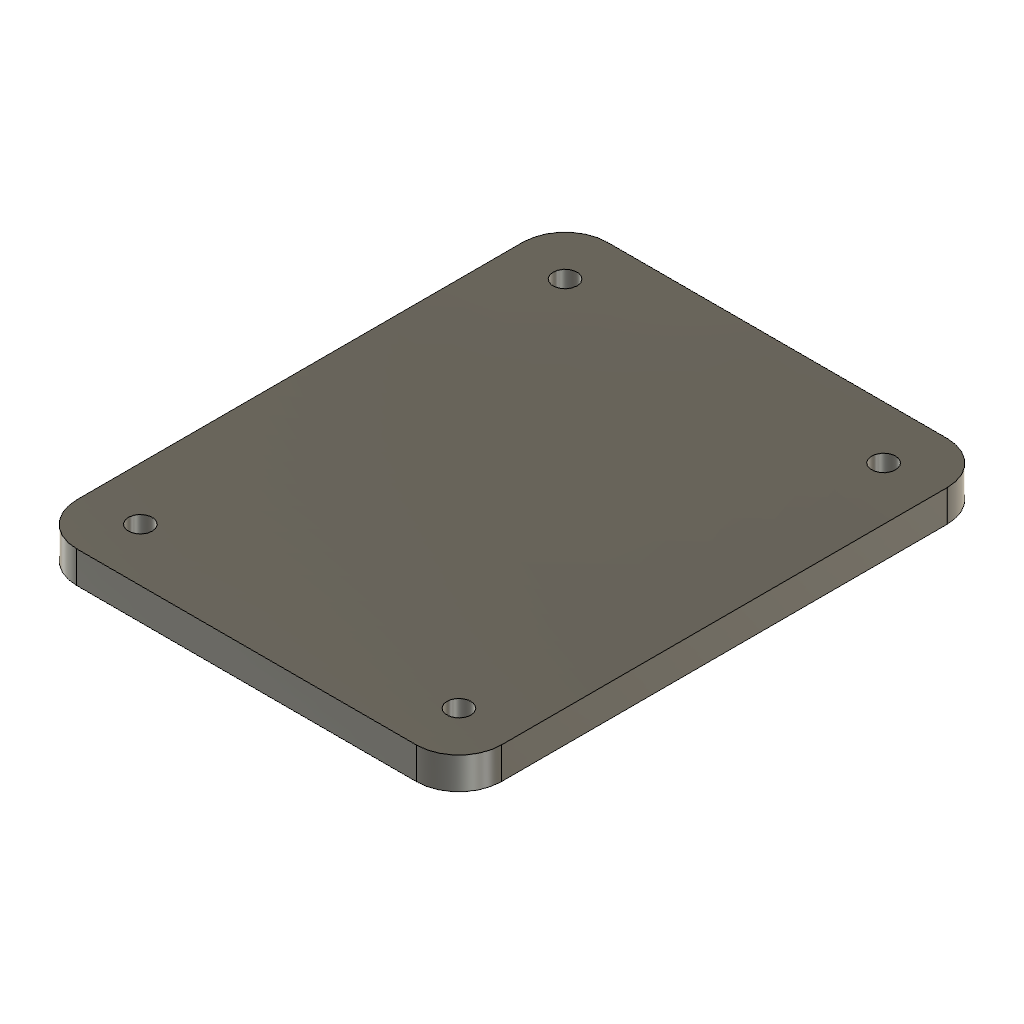
AOTS_Base_Plate_v1 (Autodesk Fusion 360 design; units mm, degrees)
part number: 2026-11-10-03-20-48-951
Autodesk Fusion 360 part; units mm, degrees
sketch "Sketch1" plane through (0, 0, 0) normal (0, 0, 1) x (1, 0, 0)
  line L0 (0, 0) -> (80, 0)
  line L1 (80, 0) -> (80, 100)
  line L2 (80, 100) -> (0, 100)
  line L3 (0, 100) -> (0, 0)
  dimension "d1" = 80
  dimension "d2" = 100
  constraint horizontal L0
  constraint vertical L1
  constraint horizontal L2
  constraint vertical L3
  constraint coincident L0.start L3.end
  measures "d1" distance of L0.start L0.end
  measures "d2" distance of L0.start L2.end
extrude "Extrude1" add sketch "Sketch1" along normal blind 6
fillet "Fillet1" radius 8 4 edges at (80, 0, 3) (0, 0, 3) (0, 100, 3) (80, 100, 3)
sketch "Sketch2" plane through (0, 0, 6) normal (0, 0, 1) x (-1, 0, 0)
  arc A0 (-80, -92) -> (-72, -100) centre (-72, -92) ccw
  line L0 (-72, -100) -> (-8, -100)
  arc A1 (-8, -100) -> (0, -92) centre (-8, -92) ccw
  line L1 (0, -92) -> (0, -8)
  arc A2 (0, -8) -> (-8, 0) centre (-8, -8) ccw
  line L2 (-8, 0) -> (-72, 0)
  arc A3 (-72, 0) -> (-80, -8) centre (-72, -8) ccw
  line L3 (-80, -8) -> (-80, -92)
  circle A4 centre (-70, -10) radius 2.25
  circle A5 centre (-10, -10) radius 2.25
  circle A6 centre (-70, -90) radius 2.25
  circle A7 centre (-10, -90) radius 2.25
  dimension "d7" = 4.5
  dimension "d8" = 10
  dimension "d9" = 10
  dimension "d10" = 4.5
  dimension "d11" = 10
  dimension "d12" = 10
  dimension "d13" = 4.5
  dimension "d14" = 10
  dimension "d15" = 10
  dimension "d16" = 4.5
  dimension "d17" = 10
  dimension "d18" = 10
  measures "d7" diameter of A4
  measures "d8" distance of L2 A4.centre
  measures "d9" distance of L3 A4.centre
  measures "d10" diameter of A5
  measures "d11" distance of L2 A5.centre
  measures "d12" distance of L1 A5.centre
  measures "d13" diameter of A6
  measures "d14" distance of L3 A6.centre
  measures "d15" distance of L0 A6.centre
  measures "d16" diameter of A7
  measures "d17" distance of L1 A7.centre
  measures "d18" distance of L0 A7.centre
extrude "Extrude2" cut sketch "Sketch2" along normal through all and the other way through all contours A4 | A5 | A6 | A7
